Autodesk Fusion 360 part; units mm, degrees
(part 5 of 5)
ref_plane "WorkPlane16" through (0, 0, 1000) normal (0, 0, 1) x (1, 0, 0) in component "MM46 Radiator four-standoff mounting set"
sketch "M6 panel mounting clearance sketch (2) (3)" plane through (0, 0, 1000) normal (0, 0, 1) x (1, 0, 0) in component "MM46 Radiator four-standoff mounting set"
  circle A0 centre (-664, 330) radius 3.25
extrude "M6 panel mounting clearance (2)'" cut sketch "M6 panel mounting clearance sketch (2) (3)" along normal blind 32 bodies 195 196 197 198 in component "MM46 Radiator four-standoff mounting set"
ref_plane "WorkPlane9" through (0, 0, 1001) normal (0, 0, 1) x (1, 0, 0) in component "MM47 Radiator eight M6 fastener sets"
sketch "M6 nominal shank sketch (2)" plane through (0, 0, 1001) normal (0, 0, 1) x (1, 0, 0) in component "MM47 Radiator eight M6 fastener sets"
  circle A0 centre (-664, 330) radius 3
extrude "M6 nominal shank (2)" add sketch "M6 nominal shank sketch (2)" along normal blind 20.2 separate body makes body 217 in component "MM47 Radiator eight M6 fastener sets"
ref_plane "WorkPlane10" through (0, 0, 1021.2) normal (0, 0, 1) x (1, 0, 0) in component "MM47 Radiator eight M6 fastener sets"
sketch "M6 hex head sketch (2)" plane through (0, 0, 1021.2) normal (0, 0, 1) x (1, 0, 0) in component "MM47 Radiator eight M6 fastener sets"
  line L0 (-658.2265, 330) -> (-661.1132, 335)
  line L1 (-661.1132, 335) -> (-666.8868, 335)
  line L2 (-666.8868, 335) -> (-669.7735, 330)
  line L3 (-669.7735, 330) -> (-666.8868, 325)
  line L4 (-666.8868, 325) -> (-661.1132, 325)
  line L5 (-661.1132, 325) -> (-658.2265, 330)
extrude "M6 hex head (2)" add sketch "M6 hex head sketch (2)" along normal blind 4 bodies 217 in component "MM47 Radiator eight M6 fastener sets"
ref_plane "WorkPlane11" through (0, 0, 1020) normal (0, 0, 1) x (1, 0, 0) in component "MM47 Radiator eight M6 fastener sets"
sketch "M6 retaining washer sketch (2)" plane through (0, 0, 1020) normal (0, 0, 1) x (1, 0, 0) in component "MM47 Radiator eight M6 fastener sets"
  circle A0 centre (-664, 330) radius 7
  circle A1 centre (-664, 330) radius 3.25
extrude "M6 retaining washer (2)" add sketch "M6 retaining washer sketch (2)" along normal blind 1.2 separate body makes body 218 in component "MM47 Radiator eight M6 fastener sets"
ref_plane "WorkPlane12" through (0, 0, 1003) normal (0, 0, 1) x (1, 0, 0) in component "MM47 Radiator eight M6 fastener sets"
sketch "M6 hex nut sketch (2)" plane through (0, 0, 1003) normal (0, 0, 1) x (1, 0, 0) in component "MM47 Radiator eight M6 fastener sets"
  line L0 (-658.2265, 330) -> (-661.1132, 335)
  line L1 (-661.1132, 335) -> (-666.8868, 335)
  line L2 (-666.8868, 335) -> (-669.7735, 330)
  line L3 (-669.7735, 330) -> (-666.8868, 325)
  line L4 (-666.8868, 325) -> (-661.1132, 325)
  line L5 (-661.1132, 325) -> (-658.2265, 330)
  circle A0 centre (-664, 330) radius 3.25
extrude "M6 hex nut (2)" add sketch "M6 hex nut sketch (2)" along normal blind 6 separate body makes body 219 in component "MM47 Radiator eight M6 fastener sets"
ref_plane "WorkPlane21" through (0, 0, 1000) normal (0, 0, 1) x (1, 0, 0) in component "MM16 Upward-facing radiator panel"
sketch "M6 panel mounting clearance sketch (3)" plane through (0, 0, 1000) normal (0, 0, 1) x (1, 0, 0) in component "MM16 Upward-facing radiator panel"
  circle A0 centre (-636, 330) radius 3.25
extrude "M6 panel mounting clearance (3)" cut sketch "M6 panel mounting clearance sketch (3)" along normal blind 32 bodies 194 in component "MM16 Upward-facing radiator panel"
ref_plane "WorkPlane17" through (0, 0, 1000) normal (0, 0, 1) x (1, 0, 0) in component "MM46 Radiator four-standoff mounting set"
sketch "M6 panel mounting clearance sketch (3) (2)" plane through (0, 0, 1000) normal (0, 0, 1) x (1, 0, 0) in component "MM46 Radiator four-standoff mounting set"
  circle A0 centre (-636, 330) radius 3.25
extrude "M6 panel mounting clearance (3)'" cut sketch "M6 panel mounting clearance sketch (3) (2)" along normal blind 32 bodies 195 196 197 198 in component "MM46 Radiator four-standoff mounting set"
ref_plane "WorkPlane13" through (0, 0, 1001) normal (0, 0, 1) x (1, 0, 0) in component "MM47 Radiator eight M6 fastener sets"
sketch "M6 nominal shank sketch (3)" plane through (0, 0, 1001) normal (0, 0, 1) x (1, 0, 0) in component "MM47 Radiator eight M6 fastener sets"
  circle A0 centre (-636, 330) radius 3
extrude "M6 nominal shank (3)" add sketch "M6 nominal shank sketch (3)" along normal blind 20.2 separate body makes body 220 in component "MM47 Radiator eight M6 fastener sets"
ref_plane "WorkPlane14" through (0, 0, 1021.2) normal (0, 0, 1) x (1, 0, 0) in component "MM47 Radiator eight M6 fastener sets"
sketch "M6 hex head sketch (3)" plane through (0, 0, 1021.2) normal (0, 0, 1) x (1, 0, 0) in component "MM47 Radiator eight M6 fastener sets"
  line L0 (-630.2265, 330) -> (-633.1132, 335)
  line L1 (-633.1132, 335) -> (-638.8868, 335)
  line L2 (-638.8868, 335) -> (-641.7735, 330)
  line L3 (-641.7735, 330) -> (-638.8868, 325)
  line L4 (-638.8868, 325) -> (-633.1132, 325)
  line L5 (-633.1132, 325) -> (-630.2265, 330)
extrude "M6 hex head (3)" add sketch "M6 hex head sketch (3)" along normal blind 4 bodies 220 in component "MM47 Radiator eight M6 fastener sets"
ref_plane "WorkPlane15" through (0, 0, 1020) normal (0, 0, 1) x (1, 0, 0) in component "MM47 Radiator eight M6 fastener sets"
sketch "M6 retaining washer sketch (3)" plane through (0, 0, 1020) normal (0, 0, 1) x (1, 0, 0) in component "MM47 Radiator eight M6 fastener sets"
  circle A0 centre (-636, 330) radius 7
  circle A1 centre (-636, 330) radius 3.25
extrude "M6 retaining washer (3)" add sketch "M6 retaining washer sketch (3)" along normal blind 1.2 separate body makes body 221 in component "MM47 Radiator eight M6 fastener sets"
ref_plane "WorkPlane16" through (0, 0, 1003) normal (0, 0, 1) x (1, 0, 0) in component "MM47 Radiator eight M6 fastener sets"
sketch "M6 hex nut sketch (3)" plane through (0, 0, 1003) normal (0, 0, 1) x (1, 0, 0) in component "MM47 Radiator eight M6 fastener sets"
  line L0 (-630.2265, 330) -> (-633.1132, 335)
  line L1 (-633.1132, 335) -> (-638.8868, 335)
  line L2 (-638.8868, 335) -> (-641.7735, 330)
  line L3 (-641.7735, 330) -> (-638.8868, 325)
  line L4 (-638.8868, 325) -> (-633.1132, 325)
  line L5 (-633.1132, 325) -> (-630.2265, 330)
  circle A0 centre (-636, 330) radius 3.25
extrude "M6 hex nut (3)" add sketch "M6 hex nut sketch (3)" along normal blind 6 separate body makes body 222 in component "MM47 Radiator eight M6 fastener sets"
ref_plane "WorkPlane22" through (0, 0, 1000) normal (0, 0, 1) x (1, 0, 0) in component "MM16 Upward-facing radiator panel"
sketch "M6 panel mounting clearance sketch (4)" plane through (0, 0, 1000) normal (0, 0, 1) x (1, 0, 0) in component "MM16 Upward-facing radiator panel"
  circle A0 centre (636, -330) radius 3.25
extrude "M6 panel mounting clearance (4)" cut sketch "M6 panel mounting clearance sketch (4)" along normal blind 32 bodies 194 in component "MM16 Upward-facing radiator panel"
ref_plane "WorkPlane18" through (0, 0, 1000) normal (0, 0, 1) x (1, 0, 0) in component "MM46 Radiator four-standoff mounting set"
sketch "M6 panel mounting clearance sketch (4) (2)" plane through (0, 0, 1000) normal (0, 0, 1) x (1, 0, 0) in component "MM46 Radiator four-standoff mounting set"
  circle A0 centre (636, -330) radius 3.25
extrude "M6 panel mounting clearance (4)'" cut sketch "M6 panel mounting clearance sketch (4) (2)" along normal blind 32 bodies 195 196 197 198 in component "MM46 Radiator four-standoff mounting set"
ref_plane "WorkPlane17" through (0, 0, 1001) normal (0, 0, 1) x (1, 0, 0) in component "MM47 Radiator eight M6 fastener sets"
sketch "M6 nominal shank sketch (4)" plane through (0, 0, 1001) normal (0, 0, 1) x (1, 0, 0) in component "MM47 Radiator eight M6 fastener sets"
  circle A0 centre (636, -330) radius 3
extrude "M6 nominal shank (4)" add sketch "M6 nominal shank sketch (4)" along normal blind 20.2 separate body makes body 223 in component "MM47 Radiator eight M6 fastener sets"
ref_plane "WorkPlane18" through (0, 0, 1021.2) normal (0, 0, 1) x (1, 0, 0) in component "MM47 Radiator eight M6 fastener sets"
sketch "M6 hex head sketch (4)" plane through (0, 0, 1021.2) normal (0, 0, 1) x (1, 0, 0) in component "MM47 Radiator eight M6 fastener sets"
  line L0 (641.7735, -330) -> (638.8868, -325)
  line L1 (638.8868, -325) -> (633.1132, -325)
  line L2 (633.1132, -325) -> (630.2265, -330)
  line L3 (630.2265, -330) -> (633.1132, -335)
  line L4 (633.1132, -335) -> (638.8868, -335)
  line L5 (638.8868, -335) -> (641.7735, -330)
extrude "M6 hex head (4)" add sketch "M6 hex head sketch (4)" along normal blind 4 bodies 223 in component "MM47 Radiator eight M6 fastener sets"
ref_plane "WorkPlane19" through (0, 0, 1020) normal (0, 0, 1) x (1, 0, 0) in component "MM47 Radiator eight M6 fastener sets"
sketch "M6 retaining washer sketch (4)" plane through (0, 0, 1020) normal (0, 0, 1) x (1, 0, 0) in component "MM47 Radiator eight M6 fastener sets"
  circle A0 centre (636, -330) radius 7
  circle A1 centre (636, -330) radius 3.25
extrude "M6 retaining washer (4)" add sketch "M6 retaining washer sketch (4)" along normal blind 1.2 separate body makes body 224 in component "MM47 Radiator eight M6 fastener sets"
ref_plane "WorkPlane20" through (0, 0, 1003) normal (0, 0, 1) x (1, 0, 0) in component "MM47 Radiator eight M6 fastener sets"
sketch "M6 hex nut sketch (4)" plane through (0, 0, 1003) normal (0, 0, 1) x (1, 0, 0) in component "MM47 Radiator eight M6 fastener sets"
  line L0 (641.7735, -330) -> (638.8868, -325)
  line L1 (638.8868, -325) -> (633.1132, -325)
  line L2 (633.1132, -325) -> (630.2265, -330)
  line L3 (630.2265, -330) -> (633.1132, -335)
  line L4 (633.1132, -335) -> (638.8868, -335)
  line L5 (638.8868, -335) -> (641.7735, -330)
  circle A0 centre (636, -330) radius 3.25
extrude "M6 hex nut (4)" add sketch "M6 hex nut sketch (4)" along normal blind 6 separate body makes body 225 in component "MM47 Radiator eight M6 fastener sets"
ref_plane "WorkPlane23" through (0, 0, 1000) normal (0, 0, 1) x (1, 0, 0) in component "MM16 Upward-facing radiator panel"
sketch "M6 panel mounting clearance sketch (5)" plane through (0, 0, 1000) normal (0, 0, 1) x (1, 0, 0) in component "MM16 Upward-facing radiator panel"
  circle A0 centre (664, -330) radius 3.25
extrude "M6 panel mounting clearance (5)" cut sketch "M6 panel mounting clearance sketch (5)" along normal blind 32 bodies 194 in component "MM16 Upward-facing radiator panel"
ref_plane "WorkPlane19" through (0, 0, 1000) normal (0, 0, 1) x (1, 0, 0) in component "MM46 Radiator four-standoff mounting set"
sketch "M6 panel mounting clearance sketch (5) (2)" plane through (0, 0, 1000) normal (0, 0, 1) x (1, 0, 0) in component "MM46 Radiator four-standoff mounting set"
  circle A0 centre (664, -330) radius 3.25
extrude "M6 panel mounting clearance (5)'" cut sketch "M6 panel mounting clearance sketch (5) (2)" along normal blind 32 bodies 195 196 197 198 in component "MM46 Radiator four-standoff mounting set"
ref_plane "WorkPlane21" through (0, 0, 1001) normal (0, 0, 1) x (1, 0, 0) in component "MM47 Radiator eight M6 fastener sets"
sketch "M6 nominal shank sketch (5)" plane through (0, 0, 1001) normal (0, 0, 1) x (1, 0, 0) in component "MM47 Radiator eight M6 fastener sets"
  circle A0 centre (664, -330) radius 3
extrude "M6 nominal shank (5)" add sketch "M6 nominal shank sketch (5)" along normal blind 20.2 separate body makes body 226 in component "MM47 Radiator eight M6 fastener sets"
ref_plane "WorkPlane22" through (0, 0, 1021.2) normal (0, 0, 1) x (1, 0, 0) in component "MM47 Radiator eight M6 fastener sets"
sketch "M6 hex head sketch (5)" plane through (0, 0, 1021.2) normal (0, 0, 1) x (1, 0, 0) in component "MM47 Radiator eight M6 fastener sets"
  line L0 (669.7735, -330) -> (666.8868, -325)
  line L1 (666.8868, -325) -> (661.1132, -325)
  line L2 (661.1132, -325) -> (658.2265, -330)
  line L3 (658.2265, -330) -> (661.1132, -335)
  line L4 (661.1132, -335) -> (666.8868, -335)
  line L5 (666.8868, -335) -> (669.7735, -330)
extrude "M6 hex head (5)" add sketch "M6 hex head sketch (5)" along normal blind 4 bodies 226 in component "MM47 Radiator eight M6 fastener sets"
ref_plane "WorkPlane23" through (0, 0, 1020) normal (0, 0, 1) x (1, 0, 0) in component "MM47 Radiator eight M6 fastener sets"
sketch "M6 retaining washer sketch (5)" plane through (0, 0, 1020) normal (0, 0, 1) x (1, 0, 0) in component "MM47 Radiator eight M6 fastener sets"
  circle A0 centre (664, -330) radius 7
  circle A1 centre (664, -330) radius 3.25
extrude "M6 retaining washer (5)" add sketch "M6 retaining washer sketch (5)" along normal blind 1.2 separate body makes body 227 in component "MM47 Radiator eight M6 fastener sets"
ref_plane "WorkPlane24" through (0, 0, 1003) normal (0, 0, 1) x (1, 0, 0) in component "MM47 Radiator eight M6 fastener sets"
sketch "M6 hex nut sketch (5)" plane through (0, 0, 1003) normal (0, 0, 1) x (1, 0, 0) in component "MM47 Radiator eight M6 fastener sets"
  line L0 (669.7735, -330) -> (666.8868, -325)
  line L1 (666.8868, -325) -> (661.1132, -325)
  line L2 (661.1132, -325) -> (658.2265, -330)
  line L3 (658.2265, -330) -> (661.1132, -335)
  line L4 (661.1132, -335) -> (666.8868, -335)
  line L5 (666.8868, -335) -> (669.7735, -330)
  circle A0 centre (664, -330) radius 3.25
extrude "M6 hex nut (5)" add sketch "M6 hex nut sketch (5)" along normal blind 6 separate body makes body 228 in component "MM47 Radiator eight M6 fastener sets"
ref_plane "WorkPlane24" through (0, 0, 1000) normal (0, 0, 1) x (1, 0, 0) in component "MM16 Upward-facing radiator panel"
sketch "M6 panel mounting clearance sketch (6)" plane through (0, 0, 1000) normal (0, 0, 1) x (1, 0, 0) in component "MM16 Upward-facing radiator panel"
  circle A0 centre (636, 330) radius 3.25
extrude "M6 panel mounting clearance (6)" cut sketch "M6 panel mounting clearance sketch (6)" along normal blind 32 bodies 194 in component "MM16 Upward-facing radiator panel"
ref_plane "WorkPlane20" through (0, 0, 1000) normal (0, 0, 1) x (1, 0, 0) in component "MM46 Radiator four-standoff mounting set"
sketch "M6 panel mounting clearance sketch (6) (2)" plane through (0, 0, 1000) normal (0, 0, 1) x (1, 0, 0) in component "MM46 Radiator four-standoff mounting set"
  circle A0 centre (636, 330) radius 3.25
extrude "M6 panel mounting clearance (6)'" cut sketch "M6 panel mounting clearance sketch (6) (2)" along normal blind 32 bodies 195 196 197 198 in component "MM46 Radiator four-standoff mounting set"
ref_plane "WorkPlane25" through (0, 0, 1001) normal (0, 0, 1) x (1, 0, 0) in component "MM47 Radiator eight M6 fastener sets"
sketch "M6 nominal shank sketch (6)" plane through (0, 0, 1001) normal (0, 0, 1) x (1, 0, 0) in component "MM47 Radiator eight M6 fastener sets"
  circle A0 centre (636, 330) radius 3
extrude "M6 nominal shank (6)" add sketch "M6 nominal shank sketch (6)" along normal blind 20.2 separate body makes body 229 in component "MM47 Radiator eight M6 fastener sets"
ref_plane "WorkPlane26" through (0, 0, 1021.2) normal (0, 0, 1) x (1, 0, 0) in component "MM47 Radiator eight M6 fastener sets"
sketch "M6 hex head sketch (6)" plane through (0, 0, 1021.2) normal (0, 0, 1) x (1, 0, 0) in component "MM47 Radiator eight M6 fastener sets"
  line L0 (641.7735, 330) -> (638.8868, 335)
  line L1 (638.8868, 335) -> (633.1132, 335)
  line L2 (633.1132, 335) -> (630.2265, 330)
  line L3 (630.2265, 330) -> (633.1132, 325)
  line L4 (633.1132, 325) -> (638.8868, 325)
  line L5 (638.8868, 325) -> (641.7735, 330)
extrude "M6 hex head (6)" add sketch "M6 hex head sketch (6)" along normal blind 4 bodies 229 in component "MM47 Radiator eight M6 fastener sets"
ref_plane "WorkPlane27" through (0, 0, 1020) normal (0, 0, 1) x (1, 0, 0) in component "MM47 Radiator eight M6 fastener sets"
sketch "M6 retaining washer sketch (6)" plane through (0, 0, 1020) normal (0, 0, 1) x (1, 0, 0) in component "MM47 Radiator eight M6 fastener sets"
  circle A0 centre (636, 330) radius 7
  circle A1 centre (636, 330) radius 3.25
extrude "M6 retaining washer (6)" add sketch "M6 retaining washer sketch (6)" along normal blind 1.2 separate body makes body 230 in component "MM47 Radiator eight M6 fastener sets"
ref_plane "WorkPlane28" through (0, 0, 1003) normal (0, 0, 1) x (1, 0, 0) in component "MM47 Radiator eight M6 fastener sets"
sketch "M6 hex nut sketch (6)" plane through (0, 0, 1003) normal (0, 0, 1) x (1, 0, 0) in component "MM47 Radiator eight M6 fastener sets"
  line L0 (641.7735, 330) -> (638.8868, 335)
  line L1 (638.8868, 335) -> (633.1132, 335)
  line L2 (633.1132, 335) -> (630.2265, 330)
  line L3 (630.2265, 330) -> (633.1132, 325)
  line L4 (633.1132, 325) -> (638.8868, 325)
  line L5 (638.8868, 325) -> (641.7735, 330)
  circle A0 centre (636, 330) radius 3.25
extrude "M6 hex nut (6)" add sketch "M6 hex nut sketch (6)" along normal blind 6 separate body makes body 231 in component "MM47 Radiator eight M6 fastener sets"
ref_plane "WorkPlane25" through (0, 0, 1000) normal (0, 0, 1) x (1, 0, 0) in component "MM16 Upward-facing radiator panel"
sketch "M6 panel mounting clearance sketch (7)" plane through (0, 0, 1000) normal (0, 0, 1) x (1, 0, 0) in component "MM16 Upward-facing radiator panel"
  circle A0 centre (664, 330) radius 3.25
extrude "M6 panel mounting clearance (7)" cut sketch "M6 panel mounting clearance sketch (7)" along normal blind 32 bodies 194 in component "MM16 Upward-facing radiator panel"
ref_plane "WorkPlane21" through (0, 0, 1000) normal (0, 0, 1) x (1, 0, 0) in component "MM46 Radiator four-standoff mounting set"
sketch "M6 panel mounting clearance sketch (7) (2)" plane through (0, 0, 1000) normal (0, 0, 1) x (1, 0, 0) in component "MM46 Radiator four-standoff mounting set"
  circle A0 centre (664, 330) radius 3.25
extrude "M6 panel mounting clearance (7)'" cut sketch "M6 panel mounting clearance sketch (7) (2)" along normal blind 32 bodies 195 196 197 198 in component "MM46 Radiator four-standoff mounting set"
ref_plane "WorkPlane29" through (0, 0, 1001) normal (0, 0, 1) x (1, 0, 0) in component "MM47 Radiator eight M6 fastener sets"
sketch "M6 nominal shank sketch (7)" plane through (0, 0, 1001) normal (0, 0, 1) x (1, 0, 0) in component "MM47 Radiator eight M6 fastener sets"
  circle A0 centre (664, 330) radius 3
extrude "M6 nominal shank (7)" add sketch "M6 nominal shank sketch (7)" along normal blind 20.2 separate body makes body 232 in component "MM47 Radiator eight M6 fastener sets"
ref_plane "WorkPlane30" through (0, 0, 1021.2) normal (0, 0, 1) x (1, 0, 0) in component "MM47 Radiator eight M6 fastener sets"
sketch "M6 hex head sketch (7)" plane through (0, 0, 1021.2) normal (0, 0, 1) x (1, 0, 0) in component "MM47 Radiator eight M6 fastener sets"
  line L0 (669.7735, 330) -> (666.8868, 335)
  line L1 (666.8868, 335) -> (661.1132, 335)
  line L2 (661.1132, 335) -> (658.2265, 330)
  line L3 (658.2265, 330) -> (661.1132, 325)
  line L4 (661.1132, 325) -> (666.8868, 325)
  line L5 (666.8868, 325) -> (669.7735, 330)
extrude "M6 hex head (7)" add sketch "M6 hex head sketch (7)" along normal blind 4 bodies 232 in component "MM47 Radiator eight M6 fastener sets"
ref_plane "WorkPlane31" through (0, 0, 1020) normal (0, 0, 1) x (1, 0, 0) in component "MM47 Radiator eight M6 fastener sets"
sketch "M6 retaining washer sketch (7)" plane through (0, 0, 1020) normal (0, 0, 1) x (1, 0, 0) in component "MM47 Radiator eight M6 fastener sets"
  circle A0 centre (664, 330) radius 7
  circle A1 centre (664, 330) radius 3.25
extrude "M6 retaining washer (7)" add sketch "M6 retaining washer sketch (7)" along normal blind 1.2 separate body makes body 233 in component "MM47 Radiator eight M6 fastener sets"
ref_plane "WorkPlane32" through (0, 0, 1003) normal (0, 0, 1) x (1, 0, 0) in component "MM47 Radiator eight M6 fastener sets"
sketch "M6 hex nut sketch (7)" plane through (0, 0, 1003) normal (0, 0, 1) x (1, 0, 0) in component "MM47 Radiator eight M6 fastener sets"
  line L0 (669.7735, 330) -> (666.8868, 335)
  line L1 (666.8868, 335) -> (661.1132, 335)
  line L2 (661.1132, 335) -> (658.2265, 330)
  line L3 (658.2265, 330) -> (661.1132, 325)
  line L4 (661.1132, 325) -> (666.8868, 325)
  line L5 (666.8868, 325) -> (669.7735, 330)
  circle A0 centre (664, 330) radius 3.25
extrude "M6 hex nut (7)" add sketch "M6 hex nut sketch (7)" along normal blind 6 separate body makes body 234 in component "MM47 Radiator eight M6 fastener sets"
combine "Connected regulated heat pipe -270" operation add target body 199 tool bodies 200 in component "MM17 Four regulated heat-pipe and collector sets"
combine "Connected regulated heat pipe -90" operation add target body 201 tool bodies 202 in component "MM17 Four regulated heat-pipe and collector sets"
combine "Connected regulated heat pipe 90" operation add target body 203 tool bodies 204 in component "MM17 Four regulated heat-pipe and collector sets"
combine "Connected regulated heat pipe 270" operation add target body 205 tool bodies 206 in component "MM17 Four regulated heat-pipe and collector sets"
component "MM01 Pressure shell and neck" placed x (1, 0, 0) y (0, 1, 0) z (0, 0, 1) at (0, 0, 0)
component "MM02 Berthing flange and clear aperture" placed x (1, 0, 0) y (0, 1, 0) z (0, 0, 1) at (0, 0, 0)
component "MM03 Inward opening pressure hatch" placed x (1, 0, 0) y (0, 1, 0) z (0, 0, 1) at (0, 0, 0)
component "MM04 Twin hatch seal lands" placed x (1, 0, 0) y (0, 1, 0) z (0, 0, 1) at (0, 0, 0)
component "MM05 Hard capture latch station" placed x (1, 0, 0) y (0, 1, 0) z (0, 0, 1) at (0, 0, 0)
component "MM05 Hard capture latch station" placed x (1, 0, 0) y (0, 0.866025, 0.5) z (0, -0.5, 0.866025) at (0, 0, 0)
component "MM05 Hard capture latch station" placed x (1, 0, 0) y (0, 0.5, 0.866025) z (0, -0.866025, 0.5) at (0, 0, 0)
component "MM05 Hard capture latch station" placed x (1, 0, 0) y (0, 0, 1) z (0, -1, 0) at (0, 0, 0)
component "MM05 Hard capture latch station" placed x (1, 0, 0) y (0, -0.5, 0.866025) z (0, -0.866025, -0.5) at (0, 0, 0)
component "MM05 Hard capture latch station" placed x (1, 0, 0) y (0, -0.866025, 0.5) z (0, -0.5, -0.866025) at (0, 0, 0)
component "MM05 Hard capture latch station" placed x (1, 0, 0) y (0, -1, 0) z (0, 0, -1) at (0, 0, 0)
component "MM05 Hard capture latch station" placed x (1, 0, 0) y (0, -0.866025, -0.5) z (0, 0.5, -0.866025) at (0, 0, 0)
component "MM05 Hard capture latch station" placed x (1, 0, 0) y (0, -0.5, -0.866025) z (0, 0.866025, -0.5) at (0, 0, 0)
component "MM05 Hard capture latch station" placed x (1, 0, 0) y (0, 0, -1) z (0, 1, 0) at (0, 0, 0)
component "MM05 Hard capture latch station" placed x (1, 0, 0) y (0, 0.5, -0.866025) z (0, 0.866025, 0.5) at (0, 0, 0)
component "MM05 Hard capture latch station" placed x (1, 0, 0) y (0, 0.866025, -0.5) z (0, 0.5, 0.866025) at (0, 0, 0)
component "MM07 MLI blanket envelope" placed x (1, 0, 0) y (0, 1, 0) z (0, 0, 1) at (0, 0, 0)
component "MM08 Load spreading band -650" placed x (1, 0, 0) y (0, 1, 0) z (0, 0, 1) at (0, 0, 0)
component "MM08 Load spreading band 650" placed x (1, 0, 0) y (0, 1, 0) z (0, 0, 1) at (0, 0, 0)
component "MM09 Cargo transfer bag" placed x (1, 0, 0) y (0, 1, 0) z (0, 0, 1) at (0, -217.5, -560)
component "MM09 Cargo transfer bag" placed x (1, 0, 0) y (0, 1, 0) z (0, 0, 1) at (0, 217.5, -560)
component "MM09 Cargo transfer bag" placed x (1, 0, 0) y (0, 1, 0) z (0, 0, 1) at (0, -435, -280)
component "MM09 Cargo transfer bag" placed x (1, 0, 0) y (0, 1, 0) z (0, 0, 1) at (0, 0, -280)
component "MM09 Cargo transfer bag" placed x (1, 0, 0) y (0, 1, 0) z (0, 0, 1) at (0, 435, -280)
component "MM09 Cargo transfer bag" placed x (1, 0, 0) y (0, 1, 0) z (0, 0, 1) at (0, -435, 0)
component "MM09 Cargo transfer bag" placed x (1, 0, 0) y (0, 1, 0) z (0, 0, 1) at (0, 0, 0)
component "MM09 Cargo transfer bag" placed x (1, 0, 0) y (0, 1, 0) z (0, 0, 1) at (0, 435, 0)
component "MM09 Cargo transfer bag" placed x (1, 0, 0) y (0, 1, 0) z (0, 0, 1) at (0, -435, 280)
component "MM09 Cargo transfer bag" placed x (1, 0, 0) y (0, 1, 0) z (0, 0, 1) at (0, 0, 280)
component "MM09 Cargo transfer bag" placed x (1, 0, 0) y (0, 1, 0) z (0, 0, 1) at (0, 435, 280)
component "MM09 Cargo transfer bag" placed x (1, 0, 0) y (0, 1, 0) z (0, 0, 1) at (0, -217.5, 560)
component "MM09 Cargo transfer bag" placed x (1, 0, 0) y (0, 1, 0) z (0, 0, 1) at (0, 217.5, 560)
component "MM09 Cargo transfer bag" placed x (1, 0, 0) y (0, 1, 0) z (0, 0, 1) at (530, -217.5, -560)
component "MM09 Cargo transfer bag" placed x (1, 0, 0) y (0, 1, 0) z (0, 0, 1) at (530, 217.5, -560)
component "MM09 Cargo transfer bag" placed x (1, 0, 0) y (0, 1, 0) z (0, 0, 1) at (530, -435, -280)
component "MM09 Cargo transfer bag" placed x (1, 0, 0) y (0, 1, 0) z (0, 0, 1) at (530, 0, -280)
component "MM09 Cargo transfer bag" placed x (1, 0, 0) y (0, 1, 0) z (0, 0, 1) at (530, 435, -280)
component "MM09 Cargo transfer bag" placed x (1, 0, 0) y (0, 1, 0) z (0, 0, 1) at (530, -435, 0)
component "MM09 Cargo transfer bag" placed x (1, 0, 0) y (0, 1, 0) z (0, 0, 1) at (530, 435, 0)
component "MM09 Cargo transfer bag" placed x (1, 0, 0) y (0, 1, 0) z (0, 0, 1) at (530, -435, 280)
component "MM09 Cargo transfer bag" placed x (1, 0, 0) y (0, 1, 0) z (0, 0, 1) at (530, 0, 280)
component "MM09 Cargo transfer bag" placed x (1, 0, 0) y (0, 1, 0) z (0, 0, 1) at (530, 435, 280)
component "MM09 Cargo transfer bag" placed x (1, 0, 0) y (0, 1, 0) z (0, 0, 1) at (530, -217.5, 560)
component "MM09 Cargo transfer bag" placed x (1, 0, 0) y (0, 1, 0) z (0, 0, 1) at (530, 217.5, 560)
component "MM10 Reconfigurable CTB tray" placed x (1, 0, 0) y (0, 1, 0) z (0, 0, 1) at (0, -217.5, -560)
component "MM10 Reconfigurable CTB tray" placed x (1, 0, 0) y (0, 1, 0) z (0, 0, 1) at (0, 217.5, -560)
component "MM10 Reconfigurable CTB tray" placed x (1, 0, 0) y (0, 1, 0) z (0, 0, 1) at (0, -435, -280)
component "MM10 Reconfigurable CTB tray" placed x (1, 0, 0) y (0, 1, 0) z (0, 0, 1) at (0, 0, -280)
component "MM10 Reconfigurable CTB tray" placed x (1, 0, 0) y (0, 1, 0) z (0, 0, 1) at (0, 435, -280)
component "MM10 Reconfigurable CTB tray" placed x (1, 0, 0) y (0, 1, 0) z (0, 0, 1) at (0, -435, 0)
component "MM10 Reconfigurable CTB tray" placed x (1, 0, 0) y (0, 1, 0) z (0, 0, 1) at (0, 0, 0)
component "MM10 Reconfigurable CTB tray" placed x (1, 0, 0) y (0, 1, 0) z (0, 0, 1) at (0, 435, 0)
component "MM10 Reconfigurable CTB tray" placed x (1, 0, 0) y (0, 1, 0) z (0, 0, 1) at (0, -435, 280)
component "MM10 Reconfigurable CTB tray" placed x (1, 0, 0) y (0, 1, 0) z (0, 0, 1) at (0, 0, 280)
component "MM10 Reconfigurable CTB tray" placed x (1, 0, 0) y (0, 1, 0) z (0, 0, 1) at (0, 435, 280)
component "MM10 Reconfigurable CTB tray" placed x (1, 0, 0) y (0, 1, 0) z (0, 0, 1) at (0, -217.5, 560)
component "MM10 Reconfigurable CTB tray" placed x (1, 0, 0) y (0, 1, 0) z (0, 0, 1) at (0, 217.5, 560)
component "MM10 Reconfigurable CTB tray" placed x (1, 0, 0) y (0, 1, 0) z (0, 0, 1) at (530, -217.5, -560)
component "MM10 Reconfigurable CTB tray" placed x (1, 0, 0) y (0, 1, 0) z (0, 0, 1) at (530, 217.5, -560)
component "MM10 Reconfigurable CTB tray" placed x (1, 0, 0) y (0, 1, 0) z (0, 0, 1) at (530, -435, -280)
component "MM10 Reconfigurable CTB tray" placed x (1, 0, 0) y (0, 1, 0) z (0, 0, 1) at (530, 0, -280)
component "MM10 Reconfigurable CTB tray" placed x (1, 0, 0) y (0, 1, 0) z (0, 0, 1) at (530, 435, -280)
component "MM10 Reconfigurable CTB tray" placed x (1, 0, 0) y (0, 1, 0) z (0, 0, 1) at (530, -435, 0)
component "MM10 Reconfigurable CTB tray" placed x (1, 0, 0) y (0, 1, 0) z (0, 0, 1) at (530, 435, 0)
component "MM10 Reconfigurable CTB tray" placed x (1, 0, 0) y (0, 1, 0) z (0, 0, 1) at (530, -435, 280)
component "MM10 Reconfigurable CTB tray" placed x (1, 0, 0) y (0, 1, 0) z (0, 0, 1) at (530, 0, 280)
component "MM10 Reconfigurable CTB tray" placed x (1, 0, 0) y (0, 1, 0) z (0, 0, 1) at (530, 435, 280)
component "MM10 Reconfigurable CTB tray" placed x (1, 0, 0) y (0, 1, 0) z (0, 0, 1) at (530, -217.5, 560)
component "MM10 Reconfigurable CTB tray" placed x (1, 0, 0) y (0, 1, 0) z (0, 0, 1) at (530, 217.5, 560)
component "MM11 Rack rails and restraint stops" placed x (1, 0, 0) y (0, 1, 0) z (0, 0, 1) at (0, 0, 0)
component "MM27 Rack conveyor channel" placed x (1, 0, 0) y (0, 1, 0) z (0, 0, 1) at (0, -217.5, -560)
component "MM27 Rack conveyor channel" placed x (1, 0, 0) y (0, 1, 0) z (0, 0, 1) at (0, 217.5, -560)
component "MM27 Rack conveyor channel" placed x (1, 0, 0) y (0, 1, 0) z (0, 0, 1) at (0, -435, -280)
component "MM27 Rack conveyor channel" placed x (1, 0, 0) y (0, 1, 0) z (0, 0, 1) at (0, 0, -280)
component "MM27 Rack conveyor channel" placed x (1, 0, 0) y (0, 1, 0) z (0, 0, 1) at (0, 435, -280)
component "MM27 Rack conveyor channel" placed x (1, 0, 0) y (0, 1, 0) z (0, 0, 1) at (0, -435, 0)
component "MM27 Rack conveyor channel" placed x (1, 0, 0) y (0, 1, 0) z (0, 0, 1) at (0, 0, 0)
component "MM27 Rack conveyor channel" placed x (1, 0, 0) y (0, 1, 0) z (0, 0, 1) at (0, 435, 0)
component "MM27 Rack conveyor channel" placed x (1, 0, 0) y (0, 1, 0) z (0, 0, 1) at (0, -435, 280)
component "MM27 Rack conveyor channel" placed x (1, 0, 0) y (0, 1, 0) z (0, 0, 1) at (0, 0, 280)
component "MM27 Rack conveyor channel" placed x (1, 0, 0) y (0, 1, 0) z (0, 0, 1) at (0, 435, 280)
component "MM27 Rack conveyor channel" placed x (1, 0, 0) y (0, 1, 0) z (0, 0, 1) at (0, -217.5, 560)
component "MM27 Rack conveyor channel" placed x (1, 0, 0) y (0, 1, 0) z (0, 0, 1) at (0, 217.5, 560)
component "MM28 Sliding receiver conveyor" placed x (1, 0, 0) y (0, 1, 0) z (0, 0, 1) at (-1170, 0, 0)
component "MM13 Battery module 2 kWh -300" placed x (1, 0, 0) y (0, 1, 0) z (0, 0, 1) at (0, 0, 0)
component "MM13 Battery module 2 kWh 300" placed x (1, 0, 0) y (0, 1, 0) z (0, 0, 1) at (0, 0, 0)
component "MM14 Pressure temperature and power electronics" placed x (1, 0, 0) y (0, 1, 0) z (0, 0, 1) at (0, 0, 0)
component "MM15 Equalization isolation and relief manifold" placed x (1, 0, 0) y (0, 1, 0) z (0, 0, 1) at (200, 0, 0)
component "MM20 Cargo trolley chassis" placed x (1, 0, 0) y (0, 1, 0) z (0, 0, 1) at (0, 0, 0)
component "MM21 Compliant wheel envelope" placed x (1, 0, 0) y (0, 1, 0) z (0, 0, 1) at (-1050, -1000, -1270)
component "MM21 Compliant wheel envelope" placed x (1, 0, 0) y (0, 1, 0) z (0, 0, 1) at (-1050, 1000, -1270)
component "MM21 Compliant wheel envelope" placed x (1, 0, 0) y (0, 1, 0) z (0, 0, 1) at (0, -1000, -1270)
component "MM21 Compliant wheel envelope" placed x (1, 0, 0) y (0, 1, 0) z (0, 0, 1) at (0, 1000, -1270)
component "MM21 Compliant wheel envelope" placed x (1, 0, 0) y (0, 1, 0) z (0, 0, 1) at (1050, -1000, -1270)
component "MM21 Compliant wheel envelope" placed x (1, 0, 0) y (0, 1, 0) z (0, 0, 1) at (1050, 1000, -1270)
component "MM22 Drive motors brakes and bogie envelopes" placed x (1, 0, 0) y (0, 1, 0) z (0, 0, 1) at (0, 0, 0)
component "MM23 Trolley power and control" placed x (1, 0, 0) y (0, 1, 0) z (0, 0, 1) at (0, 0, 0)
component "MM30 Rover habitat berthing adapter" placed x (1, 0, 0) y (0, 1, 0) z (0, 0, 1) at (0, 0, 0)
component "MM12 Fixed elevator Z guides" placed x (1, 0, 0) y (0, 1, 0) z (0, 0, 1) at (0, 0, 0)
component "MM24 Elevator Z crossbeam" placed x (1, 0, 0) y (0, 1, 0) z (0, 0, 1) at (0, 0, 0)
component "MM25 Y carriage and powered receiving deck" placed x (1, 0, 0) y (0, 1, 0) z (0, 0, 1) at (0, 0, 0)
component "MM26 Folding receiving bridge" placed x (0, 0, 1) y (0, 1, 0) z (-1, 0, 0) at (-440, 0, 180)
component "MM40 Receiver fixed guide beams" placed x (1, 0, 0) y (0, 1, 0) z (0, 0, 1) at (0, 0, 0)
component "MM41 Receiver mounting stand" placed x (1, 0, 0) y (0, 1, 0) z (0, 0, 1) at (0, 0, 0)
component "REF Existing receiver structural deck ASSUMED" placed x (1, 0, 0) y (0, 1, 0) z (0, 0, 1) at (0, 0, 0)
component "MM42 Captured receiver guide carriage" placed x (1, 0, 0) y (0, 1, 0) z (0, 0, 1) at (-3220, -175, -230)
component "MM43 Receiver M8 mounting fastener set" placed x (1, 0, 0) y (0, 1, 0) z (0, 0, 1) at (-3238, -213, 0)
component "MM42 Captured receiver guide carriage" placed x (1, 0, 0) y (0, 1, 0) z (0, 0, 1) at (-3220, 175, -230)
component "MM42 Captured receiver guide carriage" placed x (1, 0, 0) y (0, 1, 0) z (0, 0, 1) at (-2910, -175, -230)
component "MM42 Captured receiver guide carriage" placed x (1, 0, 0) y (0, 1, 0) z (0, 0, 1) at (-2910, 175, -230)
component "MM43 Receiver M8 mounting fastener set" placed x (1, 0, 0) y (0, 1, 0) z (0, 0, 1) at (-3238, -137, 0)
component "MM43 Receiver M8 mounting fastener set" placed x (1, 0, 0) y (0, 1, 0) z (0, 0, 1) at (-3162, -213, 0)
component "MM43 Receiver M8 mounting fastener set" placed x (1, 0, 0) y (0, 1, 0) z (0, 0, 1) at (-3162, -137, 0)
component "MM43 Receiver M8 mounting fastener set" placed x (1, 0, 0) y (0, 1, 0) z (0, 0, 1) at (-3238, 137, 0)
component "MM43 Receiver M8 mounting fastener set" placed x (1, 0, 0) y (0, 1, 0) z (0, 0, 1) at (-3238, 213, 0)
component "MM43 Receiver M8 mounting fastener set" placed x (1, 0, 0) y (0, 1, 0) z (0, 0, 1) at (-3162, 137, 0)
component "MM43 Receiver M8 mounting fastener set" placed x (1, 0, 0) y (0, 1, 0) z (0, 0, 1) at (-3162, 213, 0)
component "MM43 Receiver M8 mounting fastener set" placed x (1, 0, 0) y (0, 1, 0) z (0, 0, 1) at (-2438, -213, 0)
component "MM43 Receiver M8 mounting fastener set" placed x (1, 0, 0) y (0, 1, 0) z (0, 0, 1) at (-2438, -137, 0)
component "MM43 Receiver M8 mounting fastener set" placed x (1, 0, 0) y (0, 1, 0) z (0, 0, 1) at (-2362, -213, 0)
component "MM43 Receiver M8 mounting fastener set" placed x (1, 0, 0) y (0, 1, 0) z (0, 0, 1) at (-2362, -137, 0)
component "MM43 Receiver M8 mounting fastener set" placed x (1, 0, 0) y (0, 1, 0) z (0, 0, 1) at (-2438, 137, 0)
component "MM43 Receiver M8 mounting fastener set" placed x (1, 0, 0) y (0, 1, 0) z (0, 0, 1) at (-2438, 213, 0)
component "MM43 Receiver M8 mounting fastener set" placed x (1, 0, 0) y (0, 1, 0) z (0, 0, 1) at (-2362, 137, 0)
component "MM43 Receiver M8 mounting fastener set" placed x (1, 0, 0) y (0, 1, 0) z (0, 0, 1) at (-2362, 213, 0)
component "MM44 Receiver screw drive and end supports" placed x (1, 0, 0) y (0, 1, 0) z (0, 0, 1) at (0, 0, 0)
component "MM45 Receiver travelling drive nut and yoke" placed x (1, 0, 0) y (0, 1, 0) z (0, 0, 1) at (-1170, 0, 0)
component "MM16 Upward-facing radiator panel" placed x (1, 0, 0) y (0, 1, 0) z (0, 0, 1) at (0, 0, 0)
component "MM46 Radiator four-standoff mounting set" placed x (1, 0, 0) y (0, 1, 0) z (0, 0, 1) at (0, 0, 0)
component "MM17 Four regulated heat-pipe and collector sets" placed x (1, 0, 0) y (0, 1, 0) z (0, 0, 1) at (0, 0, 0)
component "MM47 Radiator eight M6 fastener sets" placed x (1, 0, 0) y (0, 1, 0) z (0, 0, 1) at (0, 0, 0)
component "Untitled" placed x (1, 0, 0) y (0, 1, 0) z (0, 0, 1) at (0, 0, 0) in component "MM03 Inward opening pressure hatch"
equation "CarrierInsideDiameter = 1840 mm" comment "Baseline design reference; coordinated changes use this build script."
equation "ShellThickness = 3 mm" comment "Baseline design reference; coordinated changes use this build script."
equation "BarrelLength = 1800 mm" comment "Baseline design reference; coordinated changes use this build script."
equation "HatchClearWidth = 670 mm" comment "Baseline design reference; coordinated changes use this build script."
equation "HatchClearHeight = 470 mm" comment "Baseline design reference; coordinated changes use this build script."
equation "CTBLength = 502 mm" comment "Baseline design reference; coordinated changes use this build script."
equation "CTBWidth = 425 mm" comment "Baseline design reference; coordinated changes use this build script."
equation "CTBHeight = 248 mm" comment "Baseline design reference; coordinated changes use this build script."
equation "WheelDiameter = 500 mm" comment "Baseline design reference; coordinated changes use this build script."
